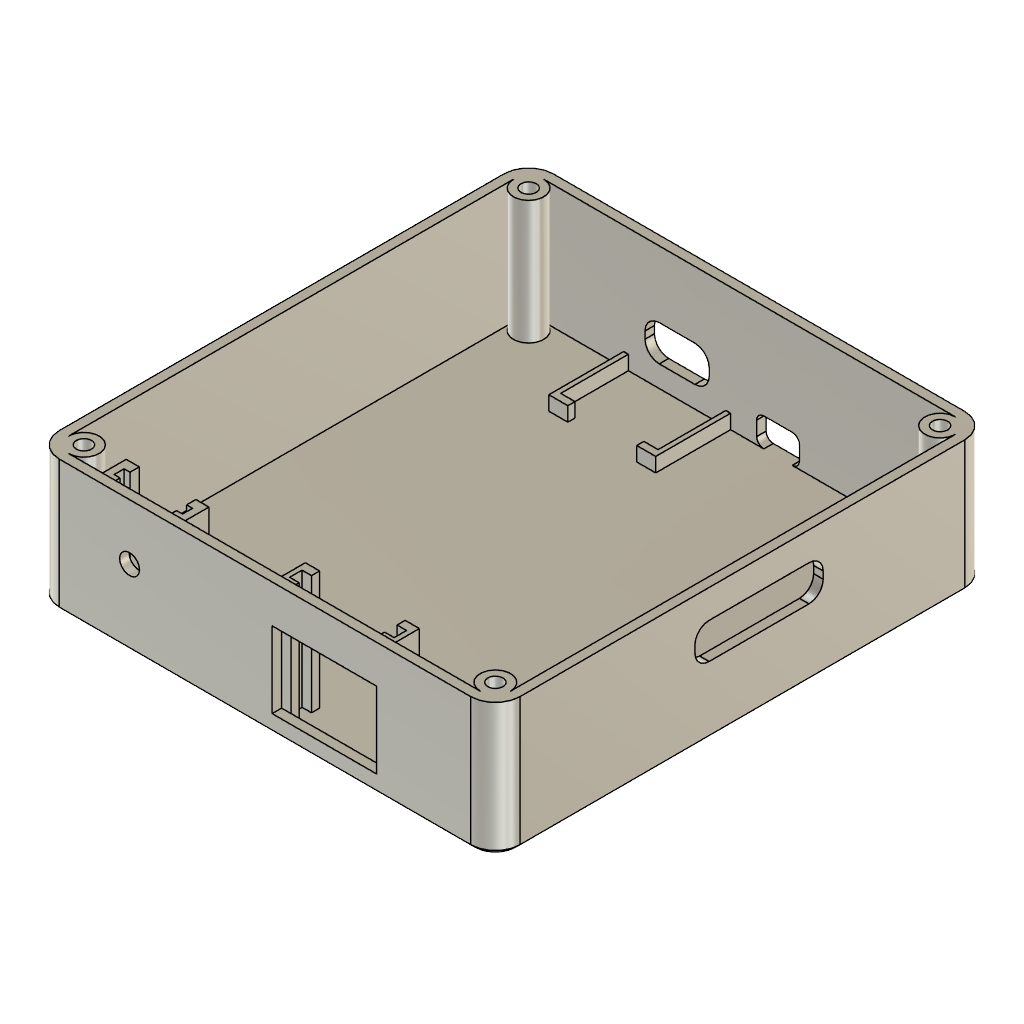
Lid (Autodesk Fusion 360 archive; units mm, degrees)
design "Case"
Autodesk Fusion 360 part; units mm, degrees
sketch "Sketch1" plane through (0, 0, 0) normal (0, 0, 1) x (1, 0, 0)
  line L0 (48.5, 52) -> (-48.5, 52)
  line L1 (-48.5, 52) -> (-48.5, -52)
  line L2 (-48.5, -52) -> (48.5, -52)
  line L3 (48.5, -52) -> (48.5, 52)
  line L4 (48.5, 52) -> (-48.5, -52) construction
  line L5 (-48.5, 52) -> (48.5, -52) construction
  line L6 (-46.5, -50) -> (46.5, -50)
  line L7 (46.5, -50) -> (46.5, 50)
  line L8 (46.5, 50) -> (-46.5, 50)
  line L9 (-46.5, 50) -> (-46.5, -50)
  circle A0 centre (-43.3, 46.8) radius 3.2
  circle A1 centre (-43.3, 46.8) radius 1.6
  circle A2 centre (43.3, 46.8) radius 3.2
  circle A3 centre (43.3, 46.8) radius 1.6
  circle A4 centre (-43.3, -46.8) radius 3.2
  circle A5 centre (-43.3, -46.8) radius 1.6
  circle A6 centre (43.3, -46.8) radius 3.2
  circle A7 centre (43.3, -46.8) radius 1.6
  dimension "d1" = 97
  dimension "d2" = 104
  dimension "d3" = -2
  dimension "d4" = 3.2
  dimension "d5" = -1.6
  dimension "d6" = 3.2
  dimension "d7" = -1.6
  dimension "d8" = 3.2
  dimension "d9" = -1.6
  dimension "d10" = 3.2
  dimension "d11" = -1.6
  constraint horizontal L0
  constraint perpendicular L0 L1
  constraint parallel L0 L2
  constraint parallel L1 L3
  constraint coincident L4 origin
  constraint coincident L5 origin
  constraint tangent L9 A0
  constraint tangent L8 A0
  constraint tangent L8 A2
  constraint tangent L7 A2
  constraint tangent L9 A4
  constraint tangent L6 A4
  constraint tangent L6 A6
  constraint tangent L7 A6
  measures "d1" distance of L1.end L2.end
  measures "d2" distance of L0.end L1.end
  measures "d4" radius of A0
  measures "d6" radius of A2
  measures "d8" radius of A4
  measures "d10" radius of A6
extrude "Extrude1" add sketch "Sketch1" along normal blind 28 contours L0 L1 L2 L3 | L6 L9 A4 | A4 | L6 L7 A6 | A6 | L8 L9 A0 | A0 | L7 L8 A2 | A2
extrude "Extrude2" add sketch "Sketch1" along normal blind 2 contours L0 L1 L2 L3 | L6 L9 A4 | L6 L7 L8 L9 A0 A2 A4 A6 | A4 | L6 L7 A6 | A6 | L8 L9 A0 | A0 | L7 L8 A2 | A2 | A1 | A3 | A5 | A7
sketch "Sketch2" plane through (0, -52, 0) normal (0, -1, 0) x (1, 0, 0)
  line L0 (48.5, 0) -> (48.5, 28)
  line L1 (48.5, 28) -> (-48.5, 28)
  line L2 (-48.5, 28) -> (-48.5, 0)
  line L3 (-48.5, 0) -> (48.5, 0)
  circle A0 centre (-28.5, 16.25) radius 2.1
  line L4 (1.5, 20) -> (23.5, 20)
  line L5 (23.5, 20) -> (23.5, 4)
  line L6 (23.5, 4) -> (1.5, 4)
  line L7 (1.5, 4) -> (1.5, 20)
  dimension "d16" = 4.2
  dimension "d17" = 16.25
  dimension "d18" = 20
  dimension "d19" = 22
  dimension "d20" = 16
  dimension "d21" = 30
  dimension "d22" = 4
  constraint horizontal L4
  constraint vertical L5
  constraint horizontal L6
  constraint vertical L7
  measures "d16" diameter of A0
  measures "d17" distance of L3 A0.centre
  measures "d18" distance of L2 A0.centre
  measures "d19" distance of L4.start L4.end
  measures "d20" distance of L4.start L6.end
  measures "d21" distance of A0.centre L7
  measures "d22" distance of L3 L6
extrude "Extrude3" cut sketch "Sketch2" against normal up to surface (2 mm away) contours A0 | L4 L5 L6 L7
sketch "Sketch3" plane through (0, 0, 0) normal (0, 0, 1) x (1, 0, 0)
  line L0 (-30.6, -50) -> (-26.4, -50)
  line L1 (23.5, -50) -> (1.5, -50)
  line L2 (21.5, -44) -> (24.5, -44)
  line L3 (24.5, -44) -> (24.5, -50)
  line L4 (24.5, -50) -> (21.5, -50)
  line L5 (21.5, -50) -> (21.5, -48.3)
  line L6 (21.5, -48.3) -> (23.5, -48.3)
  line L7 (23.5, -48.3) -> (23.5, -45.7)
  line L8 (23.5, -45.7) -> (21.5, -45.7)
  line L9 (21.5, -45.7) -> (21.5, -44)
  line L10 (1.5, -52) -> (23.5, -52)
  line L11 (43.3, -50) -> (-43.3, -50)
  line L12 (12.5, -52) -> (12.5, -43.7054) construction
  line L13 (3.5, -44) -> (0.5, -44)
  line L14 (0.5, -44) -> (0.5, -50)
  line L15 (0.5, -50) -> (3.5, -50)
  line L16 (3.5, -50) -> (3.5, -48.3)
  line L17 (3.5, -48.3) -> (1.5, -48.3)
  line L18 (1.5, -48.3) -> (1.5, -45.7)
  line L19 (1.5, -45.7) -> (3.5, -45.7)
  line L20 (3.5, -45.7) -> (3.5, -44)
  line L21 (-22.55, -44) -> (-19.8, -44)
  line L22 (-19.8, -44) -> (-19.8, -50)
  line L23 (-19.8, -50) -> (-22.55, -50)
  line L24 (-22.55, -50) -> (-22.55, -48.05)
  line L25 (-22.55, -48.05) -> (-21.3, -48.05)
  line L26 (-21.3, -48.05) -> (-21.3, -45.95)
  line L27 (-21.3, -45.95) -> (-22.55, -45.95)
  line L28 (-22.55, -45.95) -> (-22.55, -44)
  line L29 (-28.5, -50) -> (-28.5, -44.9668) construction
  line L30 (-35.7, -48.05) -> (-35.7, -45.95)
  line L31 (-34.45, -48.05) -> (-35.7, -48.05)
  line L32 (-34.45, -50) -> (-34.45, -48.05)
  line L33 (-34.45, -44) -> (-37.2, -44)
  line L34 (-35.7, -45.95) -> (-34.45, -45.95)
  line L35 (-37.2, -50) -> (-34.45, -50)
  line L36 (-37.2, -44) -> (-37.2, -50)
  line L37 (-34.45, -45.95) -> (-34.45, -44)
  point P0 (1.5, -50)
  point P1 (23.5, -50)
  point P2 (12.5, -52)
  point P3 (-28.5, -50)
  dimension "d25" = 12
  dimension "d26" = 3
  dimension "d27" = 3
  dimension "d28" = 2
  dimension "d29" = 6
  dimension "d30" = 1.7
  dimension "d31" = 1.7
  dimension "d32" = 2.75
  dimension "d33" = 8.7
  dimension "d34" = 1.25
  dimension "d35" = 1.25
  dimension "d36" = 6
  dimension "d37" = 1.95
  dimension "d38" = 1.95
  constraint horizontal L2
  constraint perpendicular L2 L3
  constraint perpendicular L3 L4
  constraint perpendicular L4 L5
  constraint perpendicular L5 L6
  constraint perpendicular L6 L7
  constraint perpendicular L7 L8
  constraint perpendicular L8 L9
  constraint midpoint P2 L10
  constraint collinear L4 L11
  constraint coincident P2 L12.start
  constraint perpendicular L10 L12
  constraint symmetric L2.start L12 L13.start
  constraint symmetric L2.end L12 L13.end
  constraint symmetric L3.end L12 L14.end
  constraint symmetric L4.end L12 L15.end
  constraint symmetric L5.end L12 L16.end
  constraint symmetric L6.end L12 L17.end
  constraint symmetric L7.end L12 L18.end
  constraint symmetric L8.end L12 L19.end
  constraint midpoint L0 P3
  constraint horizontal L21
  constraint perpendicular L21 L22
  constraint perpendicular L22 L23
  constraint perpendicular L23 L24
  constraint perpendicular L22 L25
  constraint perpendicular L25 L26
  constraint perpendicular L26 L27
  constraint perpendicular L21 L28
  constraint collinear L11 L23
  constraint coincident P3 L29.start
  constraint perpendicular L0 L29
  constraint symmetric L21.start L29 L33.start
  constraint symmetric L21.end L29 L33.end
  constraint symmetric L22.end L29 L35.start
  constraint symmetric L23.end L29 L32.start
  constraint symmetric L24.end L29 L31.start
  constraint symmetric L25.end L29 L30.start
  constraint symmetric L26.end L29 L30.end
  constraint symmetric L27.end L29 L34.end
  measures "d25" distance of L3 P2
  measures "d26" distance of L2.start L2.end
  measures "d27" distance of L3.end L4.end
  measures "d28" distance of L5.end L6.end P1
  measures "d29" distance of L2.end L3.end
  measures "d30" distance of L4.end L5.end P1
  measures "d31" distance of L2.start L8.end
  measures "d32" distance of L21.start L21.end
  measures "d33" distance of P3 L22
  measures "d34" distance of L26.end L27.end
  measures "d35" distance of L24.end L25.end
  measures "d36" distance of L21.end L22.end
  measures "d37" distance of L23.end L24.end
  measures "d38" distance of L21.start L27.end
extrude "Extrude4" add sketch "Sketch3" along normal blind 25 from surface at 2
sketch "Sketch4" plane through (0, 0, 2) normal (0, 0, 1) x (-1, 0, 0)
  line L0 (-24.5, 44) -> (-24.5, 50)
  line L1 (-24.5, 50) -> (-43.3, 50)
  arc A0 (-46.5, 46.8) -> (-43.3, 50) centre (-43.3, 46.8) ccw
  line L2 (-46.5, 46.8) -> (-46.5, -46.8)
  arc A1 (-43.3, -50) -> (-46.5, -46.8) centre (-43.3, -46.8) ccw
  line L3 (-43.3, -50) -> (43.3, -50)
  arc A2 (46.5, -46.8) -> (43.3, -50) centre (43.3, -46.8) ccw
  line L4 (46.5, -46.8) -> (46.5, 46.8)
  arc A3 (43.3, 50) -> (46.5, 46.8) centre (43.3, 46.8) ccw
  line L5 (43.3, 50) -> (37.2, 50)
  line L6 (37.2, 50) -> (37.2, 44)
  line L7 (37.2, 44) -> (34.45, 44)
  line L8 (34.45, 44) -> (34.45, 45.95)
  line L9 (34.45, 45.95) -> (35.7, 45.95)
  line L10 (35.7, 45.95) -> (35.7, 48.05)
  line L11 (35.7, 48.05) -> (34.45, 48.05)
  line L12 (34.45, 48.05) -> (34.45, 50)
  line L13 (34.45, 50) -> (22.55, 50)
  line L14 (22.55, 50) -> (22.55, 48.05)
  line L15 (22.55, 48.05) -> (21.3, 48.05)
  line L16 (21.3, 48.05) -> (21.3, 45.95)
  line L17 (21.3, 45.95) -> (22.55, 45.95)
  line L18 (22.55, 45.95) -> (22.55, 44)
  line L19 (22.55, 44) -> (19.8, 44)
  line L20 (19.8, 44) -> (19.8, 50)
  line L21 (19.8, 50) -> (-0.5, 50)
  line L22 (-0.5, 50) -> (-0.5, 44)
  line L23 (-0.5, 44) -> (-3.5, 44)
  line L24 (-3.5, 44) -> (-3.5, 45.7)
  line L25 (-3.5, 45.7) -> (-1.5, 45.7)
  line L26 (-1.5, 45.7) -> (-1.5, 48.3)
  line L27 (-1.5, 48.3) -> (-3.5, 48.3)
  line L28 (-3.5, 48.3) -> (-3.5, 50)
  line L29 (-3.5, 50) -> (-21.5, 50)
  line L30 (-21.5, 50) -> (-21.5, 48.3)
  line L31 (-21.5, 48.3) -> (-23.5, 48.3)
  line L32 (-23.5, 48.3) -> (-23.5, 45.7)
  line L33 (-23.5, 45.7) -> (-21.5, 45.7)
  line L34 (-21.5, 45.7) -> (-21.5, 44)
  line L35 (-21.5, 44) -> (-24.5, 44)
  line L36 (26.5, -50) -> (26.5, -34.25)
  line L37 (26.5, -34.25) -> (22.5, -34.25)
  line L38 (22.5, -34.25) -> (22.5, -35.75)
  line L39 (22.5, -35.75) -> (25.5, -35.75)
  line L40 (25.5, -35.75) -> (25.5, -50)
  line L41 (5, -50) -> (5, -35.75)
  line L42 (5, -35.75) -> (8, -35.75)
  line L43 (8, -35.75) -> (8, -34.25)
  line L44 (8, -34.25) -> (4, -34.25)
  line L45 (4, -34.25) -> (4, -50)
  dimension "d42" = 1.5
  dimension "d43" = 15.75
  dimension "d44" = 3
  dimension "d45" = 1.5
  dimension "d46" = 15.75
  dimension "d47" = 3
  dimension "d48" = 20.5
  dimension "d49" = 4
  dimension "d50" = 4
  dimension "d51" = 20
  constraint coincident L3 L36.start
  constraint perpendicular L3 L36
  constraint perpendicular L36 L37
  constraint perpendicular L3 L38
  constraint perpendicular L38 L39
  constraint coincident L3 L40.end
  constraint perpendicular L3 L40
  constraint coincident L3 L41.start
  constraint perpendicular L3 L41
  constraint perpendicular L41 L42
  constraint perpendicular L42 L43
  constraint perpendicular L43 L44
  constraint coincident L3 L45.end
  constraint perpendicular L3 L45
  measures "d42" distance of L37.end L38.end
  measures "d43" distance of L36.start L36.end
  measures "d44" distance of L38.end L39.end
  measures "d45" distance of L42.end L43.end
  measures "d46" distance of L44.end L45.end
  measures "d47" distance of L41.end L42.end
  measures "d48" distance of L40 L41
  measures "d49" distance of L36.end L37.end
  measures "d50" distance of L43.end L44.end
  measures "d51" distance of L4 L36
extrude "Extrude5" add sketch "Sketch4" along normal blind 3 contours L3 L41 L42 L43 L44 L45 | L3 L36 L37 L38 L39 L40
sketch "Sketch5" plane through (0, 52, 0) normal (0, 1, 0) x (-1, 0, 0)
  line L0 (48.5, 0) -> (48.5, 28)
  line L1 (48.5, 28) -> (-48.5, 28)
  line L2 (-48.5, 28) -> (-48.5, 0)
  line L3 (-48.5, 0) -> (48.5, 0)
  line L4 (5, 2) -> (5, 5)
  line L5 (5, 5) -> (5, 2)
  line L6 (25.5, 2) -> (25.5, 5)
  line L7 (25.5, 5) -> (25.5, 2)
  line L8 (8.5, 14) -> (22, 14)
  line L9 (22, 14) -> (22, 6.5)
  line L10 (22, 6.5) -> (8.5, 6.5)
  line L11 (8.5, 6.5) -> (8.5, 14)
  line L12 (25.5, 2) -> (5, 2)
  line L13 (-10.5, 8) -> (-1.5, 8)
  line L14 (-1.5, 8) -> (-1.5, 2)
  line L15 (-1.5, 2) -> (-10.5, 2)
  line L16 (-10.5, 2) -> (-10.5, 8)
  line L17 (-0.5, 2) -> (19.8, 2)
  dimension "d54" = 13.5
  dimension "d55" = 7.5
  dimension "d56" = 3.5
  dimension "d57" = 4.5
  dimension "d58" = 6
  dimension "d59" = 9
  dimension "d60" = 10
  dimension "d75" = 3.5
  dimension "d76" = 20.5
  constraint horizontal L8
  constraint vertical L9
  constraint horizontal L10
  constraint vertical L11
  constraint horizontal L13
  constraint vertical L14
  constraint horizontal L15
  constraint vertical L16
  constraint coincident L14.end L17
  measures "d54" distance of L8.start L8.end
  measures "d55" distance of L8.start L10.end
  measures "d56" distance of L5 L11
  measures "d57" distance of L10 L12
  measures "d58" distance of L13.end L14.end
  measures "d59" distance of L13.start L13.end
  measures "d60" distance of L11 L14
  measures "d75" distance of L7 L9
  measures "d76" distance of L6.start L4.start
extrude "Extrude6" cut sketch "Sketch5" against normal up to surface (2 mm away) contours L8 L9 L10 L11 | L13 L14 L15 L16
sketch "Sketch6" plane through (48.5, 0, 0) normal (1, 0, 0) x (0, 1, 0)
  line L0 (52, 0) -> (52, 28)
  line L1 (52, 28) -> (-52, 28)
  line L2 (-52, 28) -> (-52, 0)
  line L3 (-52, 0) -> (52, 0)
  line L4 (-10, 22) -> (17, 22)
  line L5 (17, 22) -> (17, 14.5)
  line L6 (17, 14.5) -> (-10, 14.5)
  line L7 (-10, 14.5) -> (-10, 22)
  dimension "d63" = 27
  dimension "d64" = 7.5
  dimension "d65" = 14.5
  dimension "d66" = 35
  constraint horizontal L4
  constraint vertical L5
  constraint horizontal L6
  constraint vertical L7
  measures "d63" distance of L4.start L4.end
  measures "d64" distance of L4.start L6.end
  measures "d65" distance of L3 L6
  measures "d66" distance of L0 L5
extrude "Extrude7" cut sketch "Sketch6" against normal up to surface (2 mm away) contours L4 L5 L6 L7
fillet "Fillet1" radius 3 4 edges at (47.5, -10, 22) (47.5, -10, 14.5) (47.5, 17, 14.5) (47.5, 17, 22)
fillet "Fillet1" radius 1.5 4 edges at (1.5, 51, 8) (10.5, 51, 8) (1.5, 51, 2) (10.5, 51, 2)
fillet "Fillet1" radius 3 4 edges at (-8.5, 51, 6.5) (-8.5, 51, 14) (-22, 51, 14) (-22, 51, 6.5)
fillet "Fillet1" radius 5.2 4 edges at (48.5, 52, 14) (-48.5, 52, 14) (-48.5, -52, 14) (48.5, -52, 14)
chamfer "Chamfer1" distance 1 angle 45 4 edges at (0, 52, 0) (48.5, 0, 0) (-48.5, 0, 0) (0, -52, 0) tangent chain off
equation "d6 = d4"
equation "d7 = d5"
equation "d8 = d4"
equation "d9 = d5"
equation "d10 = d4"
equation "d11 = d5"
equation "d27 = d26"
equation "d31 = d30"
equation "d34 = d35"
equation "d35 = d32 - 1.5 mm"
equation "d37 = ( d36 - 2.1 mm ) / 2"
equation "d38 = d37"
equation "d43 = 14.25 mm + d42"
equation "d45 = d42"
equation "d46 = d43"
equation "d47 = d44"
equation "d49 = d44 + 1 mm"
equation "d50 = d49"
equation "d56 = ( d76 - d54 ) / 2"
